badge snap (Autodesk Fusion 360 design; units mm, degrees)
Autodesk Fusion 360 part; units mm, degrees
sketch "Sketch1" plane through (0, 0, 0) normal (0, 1, 0) x (1, 0, 0)
  line L0 (5, -2.5) -> (-5, -2.5)
  line L1 (-5, -2.5) -> (-5, 2.5)
  line L2 (-5, 2.5) -> (5, 2.5)
  line L3 (5, 2.5) -> (5, -2.5)
  line L4 (7, -2.5) -> (-7, -2.5)
  line L5 (-7, -2.5) -> (-7, 2.5)
  line L6 (-7, 2.5) -> (7, 2.5)
  line L7 (7, 2.5) -> (7, -2.5)
extrude "Extrude1" add sketch "Sketch1" along normal blind 2 makes body 1
extrude "Extrude2" add sketch "Sketch1" against normal blind 6 contours L3 L4 L6 L7 | L1 L4 L5 L6 bodies 1
sketch "Sketch2" plane through (0, 0, -2.5) normal (0, 0, -1) x (-1, 0, 0)
  line L0 (7, -6) -> (7, 2)
  line L1 (7, 2) -> (-7, 2)
  line L2 (-7, 2) -> (-7, -6)
  line L3 (-7, -6) -> (-5, -6)
  line L4 (-5, -6) -> (-5, 0)
  line L5 (-5, 0) -> (5, 0)
  line L6 (5, 0) -> (5, -6)
  line L7 (5, -6) -> (7, -6)
  line L8 (-5, -6) -> (-5.0691, -4.0012)
  line L9 (-5, -6) -> (-3.8211, -3.958)
  line L10 (-5, -6) -> (-2.6906, -6) construction
  line L11 (-3.8211, -3.958) -> (-5.0691, -4.0012)
  line L12 (-3.8211, -3.958) -> (-5.0691, -4.0012)
  line L13 (5, -6) -> (5.0691, -4.0012)
  line L14 (5, -6) -> (3.8211, -3.958)
  line L15 (5, -6) -> (7.3094, -6) construction
  line L16 (3.8211, -3.958) -> (5.0691, -4.0012)
  dimension "d8" = 2
  dimension "d9" = 60
  dimension "d10" = 2
  dimension "d11" = 120
  constraint coincident L3.end L4.start
  constraint horizontal L10
  constraint perpendicular L8 L11
  constraint coincident L6.end L7.start
  constraint horizontal L15
  constraint perpendicular L13 L16
  measures "d8" distance of L3.end L8.end
  measures "d9" angle of L9 L10
  measures "d10" distance of L6.end L13.end
  measures "d11" angle of L14 L15
extrude "Extrude3" add sketch "Sketch2" against normal blind 5 contours L6 L14 L16 | L6 L13 L16 | L4 L9 L11 L12 bodies 1
chamfer "Chamfer1" distance 2 angle 45 2 edges at (7, 2, 0) (-7, 2, 0) tangent chain off on bodies 1
chamfer "Chamfer2" distance 1.5 angle 45 2 edges at (7, -6, 0) (-7, -6, 0) tangent chain off on bodies 1
fillet "Fillet2" radius 3 4 edges at (-7, -4.5, 0) (-7, 0, 0) (7, -4.5, 0) (7, 0, 0) on bodies 1
sketch "Sketch3" plane through (0, 0, 0) normal (0, 1, 0) x (1, 0, 0)
  line L0 (-5, 16.5) -> (5, 16.5)
  line L1 (5, 16.5) -> (5, 11.5)
  line L2 (5, 11.5) -> (-5, 11.5)
  line L3 (-5, 11.5) -> (-5, 16.5)
  line L4 (-5, 16.5) -> (5, 11.5) construction
  line L5 (5, 16.5) -> (-5, 11.5) construction
  point P0 (0, 14)
  dimension "d18" = 10
  dimension "d19" = 5
  constraint perpendicular L0 L1
  constraint parallel L0 L2
  constraint parallel L1 L3
  constraint horizontal L0
  constraint coincident L4 P0
  constraint coincident L5 P0
  measures "d18" distance of L1.end L2.end
  measures "d19" distance of L0.end L1.end
extrude "Extrude4" add sketch "Sketch3" along normal blind 2 separate body makes body 2
fillet "Fillet3" radius 0.5 2 edges at (-3.8211, -3.958, 0) (3.8211, -3.958, 0) on bodies 1
sketch "Sketch4" plane through (0, 0, -16.5) normal (0, 0, -1) x (-1, 0, 0)
  line L0 (-5, 0) -> (5, 0)
  line L1 (5, 0) -> (5, 2)
  line L2 (5, 2) -> (-5, 2)
  line L3 (-5, 2) -> (-5, 0)
  line L4 (-5, 2) -> (-5, 0)
  line L5 (-5, 0) -> (-6.1547, 2)
  line L6 (-5, 0) -> (-2.6906, 0) construction
  line L7 (-6.1547, 2) -> (-5, 2)
  line L8 (5, 2) -> (5, 0)
  line L9 (5, 0) -> (6.1547, 2)
  line L10 (6.1547, 2) -> (5, 2)
  dimension "d23" = 120
  dimension "d24" = 60
  constraint coincident L2.end L3.start
  constraint coincident L0.start L3.end
  constraint horizontal L6
  constraint perpendicular L4 L7
  constraint coincident L1.end L2.start
  constraint coincident L0.end L1.start
  constraint perpendicular L8 L10
  measures "d23" angle of L5 L6
  measures "d24" angle of L6 L9
extrude "Extrude5" add sketch "Sketch4" against normal blind 5 contours L3 L4 L5 L7 | L1 L8 L9 L10 bodies 2
fillet "Fillet4" radius 0.25 2 edges at (6.1547, 2, -14) (-6.1547, 2, -14) on bodies 2
sketch "Sketch5" plane through (0, 0, -2.5) normal (0, 0, -1) x (-1, 0, 0)
  arc A0 (-4.2719, -4.7389) -> (-4.7222, -3.9892) centre (-4.7049, -4.4889) ccw
  line L0 (-4.7222, -3.9892) -> (-5, -3.9988)
  line L1 (-5, -3.9988) -> (-5, 0)
  line L2 (-5, 0) -> (5, 0)
  line L3 (5, 0) -> (5, -3.9988)
  line L4 (5, -3.9988) -> (4.7222, -3.9892)
  arc A1 (4.7222, -3.9892) -> (4.2719, -4.7389) centre (4.7049, -4.4889) ccw
  line L5 (4.2719, -4.7389) -> (5, -6)
  line L6 (5, -6) -> (5.5, -6)
  line L7 (5.5, -6) -> (6.1213, -5.3787)
  arc A2 (6.1213, -5.3787) -> (7, -3.2574) centre (4, -3.2574) ccw
  line L8 (7, -3.2574) -> (7, -1.2426)
  arc A3 (7, -1.2426) -> (6.1213, 0.8787) centre (4, -1.2426) ccw
  line L9 (6.1213, 0.8787) -> (5, 2)
  line L10 (5, 2) -> (-5, 2)
  line L11 (-5, 2) -> (-6.1213, 0.8787)
  arc A4 (-6.1213, 0.8787) -> (-7, -1.2426) centre (-4, -1.2426) ccw
  line L12 (-7, -1.2426) -> (-7, -3.2574)
  arc A5 (-7, -3.2574) -> (-6.1213, -5.3787) centre (-4, -3.2574) ccw
  line L13 (-6.1213, -5.3787) -> (-5.5, -6)
  line L14 (-5.5, -6) -> (-5, -6)
  line L15 (-5, -6) -> (-4.2719, -4.7389)
  line L16 (-5, -3.9988) -> (-5, -1.9988)
  line L17 (-4.2719, -4.7389) -> (-5, -1.9988)
  dimension "d28" = 2
  constraint coincident L0.end L1.start
  constraint coincident A0.start L15.end
  measures "d28" distance of L0.end L16.end
extrude "Extrude6" add sketch "Sketch5" against normal blind 1 contours A0 L0 L1 L16 L17 bodies 1
sketch "Sketch6" plane through (0, 0, -2.5) normal (0, 0, -1) x (-1, 0, 0)
  line L0 (-5, -1.9988) -> (-5, 0)
  line L1 (-5, 0) -> (5, 0)
  line L2 (5, 0) -> (5, -3.9988)
  line L3 (5, -3.9988) -> (4.7222, -3.9892)
  arc A0 (4.7222, -3.9892) -> (4.2719, -4.7389) centre (4.7049, -4.4889) ccw
  line L4 (4.2719, -4.7389) -> (5, -6)
  line L5 (5, -6) -> (5.5, -6)
  line L6 (5.5, -6) -> (6.1213, -5.3787)
  arc A1 (6.1213, -5.3787) -> (7, -3.2574) centre (4, -3.2574) ccw
  line L7 (7, -3.2574) -> (7, -1.2426)
  arc A2 (7, -1.2426) -> (6.1213, 0.8787) centre (4, -1.2426) ccw
  line L8 (6.1213, 0.8787) -> (5, 2)
  line L9 (5, 2) -> (-5, 2)
  line L10 (-5, 2) -> (-6.1213, 0.8787)
  arc A3 (-6.1213, 0.8787) -> (-7, -1.2426) centre (-4, -1.2426) ccw
  line L11 (-7, -1.2426) -> (-7, -3.2574)
  arc A4 (-7, -3.2574) -> (-6.1213, -5.3787) centre (-4, -3.2574) ccw
  line L12 (-6.1213, -5.3787) -> (-5.5, -6)
  line L13 (-5.5, -6) -> (-5, -6)
  line L14 (-5, -6) -> (-4.2719, -4.7389)
  arc A5 (-4.2719, -4.7389) -> (-4.4531, -4.0569) centre (-4.7049, -4.4889) ccw
  line L15 (-4.4531, -4.0569) -> (-5, -1.9988)
  line L16 (5, -3.9988) -> (5, -1.9988)
  line L17 (5, -1.9988) -> (4.2719, -4.7389)
  dimension "d31" = 2
  constraint coincident L2.end L3.start
  constraint coincident A0.end L4.start
  measures "d31" distance of L2.end L16.end
extrude "Extrude7" add sketch "Sketch6" against normal blind 1 contours L2 L3 A0 L16 L17 bodies 1
sketch "Sketch7" plane through (0, 0, 2.5) normal (0, 0, 1) x (1, 0, 0)
  arc A0 (4.7222, -3.9892) -> (4.2719, -4.7389) centre (4.7049, -4.4889) ccw
  line L0 (4.2719, -4.7389) -> (5, -6)
  line L1 (5, -6) -> (5.5, -6)
  line L2 (5.5, -6) -> (6.1213, -5.3787)
  arc A1 (6.1213, -5.3787) -> (7, -3.2574) centre (4, -3.2574) ccw
  line L3 (7, -3.2574) -> (7, -1.2426)
  arc A2 (7, -1.2426) -> (6.1213, 0.8787) centre (4, -1.2426) ccw
  line L4 (6.1213, 0.8787) -> (5, 2)
  line L5 (5, 2) -> (-5, 2)
  line L6 (-5, 2) -> (-6.1213, 0.8787)
  arc A3 (-6.1213, 0.8787) -> (-7, -1.2426) centre (-4, -1.2426) ccw
  line L7 (-7, -1.2426) -> (-7, -3.2574)
  arc A4 (-7, -3.2574) -> (-6.1213, -5.3787) centre (-4, -3.2574) ccw
  line L8 (-6.1213, -5.3787) -> (-5.5, -6)
  line L9 (-5.5, -6) -> (-5, -6)
  line L10 (-5, -6) -> (-4.2719, -4.7389)
  arc A5 (-4.2719, -4.7389) -> (-4.7222, -3.9892) centre (-4.7049, -4.4889) ccw
  line L11 (-4.7222, -3.9892) -> (-5, -3.9988)
  line L12 (-5, -3.9988) -> (-5, 0)
  line L13 (-5, 0) -> (5, 0)
  line L14 (5, 0) -> (5, -3.9988)
  line L15 (5, -3.9988) -> (4.7222, -3.9892)
  line L16 (-5, -1.9988) -> (-4.2719, -4.7389)
  line L17 (5, -1.9988) -> (4.2719, -4.7389)
  point P0 (-5, -1.9988)
  point P1 (5, -1.9988)
  constraint coincident P0 L16.start
  constraint coincident L10.end A5.start
  constraint coincident P1 L17.start
  constraint coincident A0.end L0.start
extrude "Extrude8" add sketch "Sketch7" against normal blind 1 contours A0 L14 L15 L17 | A5 L11 L12 L16 bodies 1
sketch "Sketch8" plane through (0, 0, -16.5) normal (0, 0, -1) x (-1, 0, 0)
  arc A0 (5.9382, 1.625) -> (5.7217, 2) centre (5.7217, 1.75) ccw
  line L0 (5.7217, 2) -> (-5.7217, 2)
  arc A1 (-5.7217, 2) -> (-5.9382, 1.625) centre (-5.7217, 1.75) ccw
  line L1 (-5.9382, 1.625) -> (-5, 0)
  line L2 (-5, 0) -> (5, 0)
  line L3 (5, 0) -> (5.9382, 1.625)
extrude "Extrude9" cut sketch "Sketch8" against normal blind 2 bodies 2
